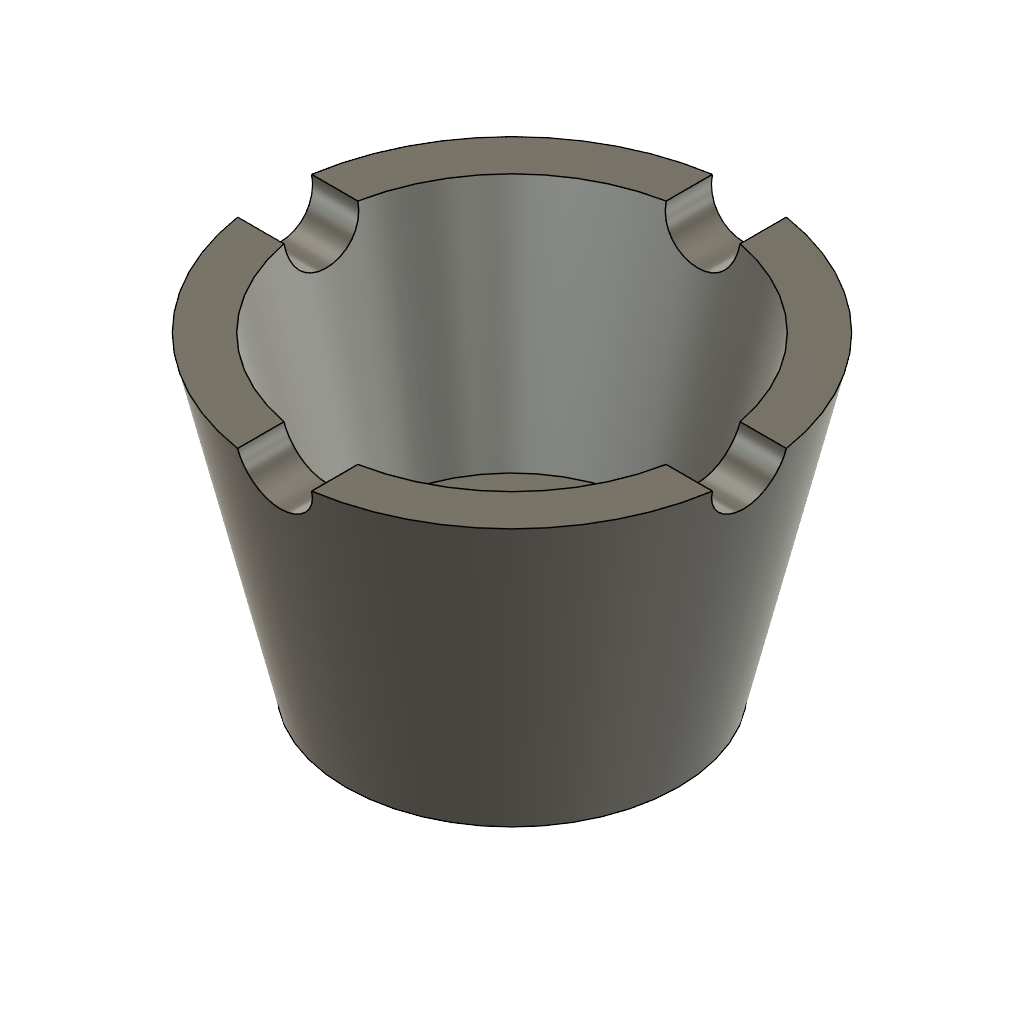
cup (Autodesk Fusion 360 design; units mm, degrees)
part number: 2026-11-04-17-32-58-312
Autodesk Fusion 360 part; units mm, degrees
sketch "Sketch1" plane through (0, 0, 0) normal (0, 0, 1) x (1, 0, 0)
  line L0 (0, 0) -> (22.5, 0)
  line L1 (0, 42) -> (32.5, 42)
  line L2 (32.5, 42) -> (22.5, 0)
  line L3 (0, 12) -> (47.3673, 12) construction
  line L4 (26.3323, 42) -> (13.6695, -11.1837) construction
  line L5 (0, 12) -> (19.1894, 12)
  line L6 (26.3323, 42) -> (19.1894, 12)
  line L7 (0, 42) -> (0, 0)
  dimension "d1" = 22.5
  dimension "d2" = 32.5
  dimension "d3" = 42
  dimension "d5" = 6
  dimension "d20" = 12
  constraint coincident L0.start L7.end
  constraint horizontal L0
  constraint horizontal L1
  constraint parallel L0 L3
  constraint coincident L1 L4.start
  constraint parallel L2 L4
  constraint coincident L3 L5.end
  constraint coincident L4 L5.end
  constraint perpendicular L0 L7
  measures "d1" distance of L0.start L0.end
  measures "d2" distance of L1.start L1.end
  measures "d3" distance of L0.start L1.start
  measures "d5" distance of L2 L4
  measures "d20" distance of L0 L5.end
revolve "Revolve1" add sketch "Sketch1" angle 360 about axis through (0, 42, 0) along (0, -1, 0) contours L0 L1 L2 L5 L6 L7
sketch "Sketch2" plane through (0, 0, 0) normal (0, -1, 0) x (1, 0, 0)
  circle A0 centre (0, 0) radius 22.5
  circle A1 centre (0, 0) radius 12
  dimension "d7" = 24
  constraint coincident A0.centre A1.centre
  measures "d7" diameter of A1
extrude "Extrude1" cut sketch "Sketch2" against normal blind 12 contours A1
ref_plane "WorkPlane1" through (-10.8313, 42, 4.8968) normal (0, 0, 1) x (0, 1, 0)
sketch "Sketch3" plane through (0, 0, 4.8968) normal (0, 0, 1) x (1, 0, 0)
  circle A0 centre (0, 42) radius 5
  point P0 (32.5, 42)
  dimension "d12" = 10
  dimension "d13" = 42
  dimension "d14" = 32.5
  measures "d12" diameter of A0
  measures "d13" distance of origin A0.centre
  measures "d14" distance of A0.centre P0
extrude "Extrude2" cut sketch "Sketch3" against normal blind 40
pattern_circular "C-Pattern1" count 4 over 360 about axis through (0, 63, 0) along (0, -1, 0) of "Extrude2"
